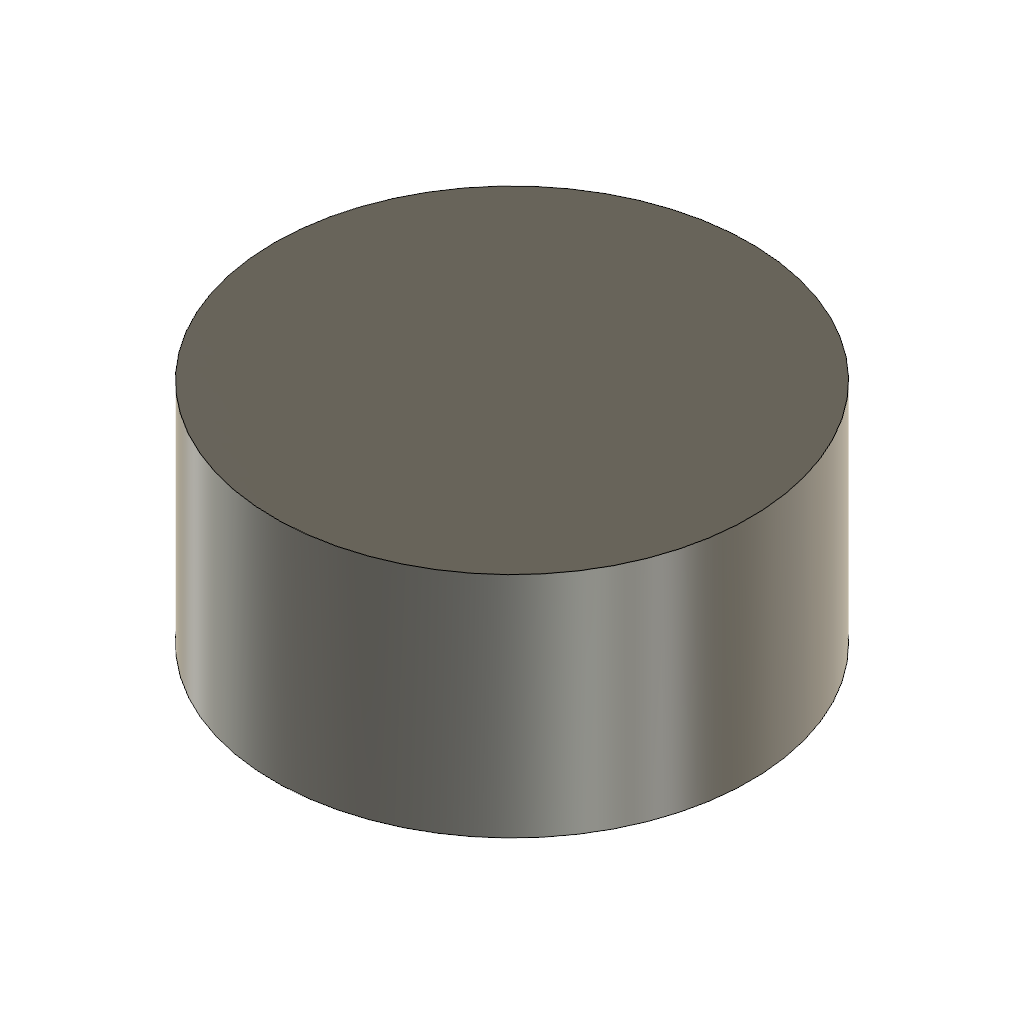
vendor_production_circle_extrusion (Autodesk Fusion 360 design; units mm, degrees)
Autodesk Fusion 360 part; units mm, degrees
sketch "Authored Circle" plane through (0, 0, 0) normal (0, 0, 1) x (1, 0, 0)
  circle A0 centre (0, 0) radius 18
extrude "Extrude1" add sketch "Authored Circle" along normal blind 17.25
equation "authoredLength = 17.25 mm" comment "Production native codec acceptance"
equation "d2 = authoredLength"
